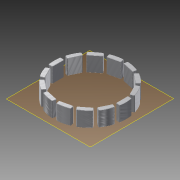
# Autodesk Inventor part: Magnets
Saved by Autodesk Inventor 2013 (Build 170138000, 138)
## iProperties
Created: 2013-09-29
Part Number: Magnets
Material: Generic
Document SubType Name: Modeling
Designer: Hunter
Density: 1 g/cm^3
Author: Hunter
Autodesk Inventor part; units mm, degrees
ref_plane "YZ Plane" through (0, 0, 0) normal (1, 0, 0) x (0, 1, 0)
ref_plane "XZ Plane" through (0, 0, 0) normal (0, 1, 0) x (-1, 0, 0)
ref_plane "XY Plane" through (0, 0, 0) normal (0, 0, 1) x (1, 0, 0)
ref_plane "Work Plane1" through (-207.9007, 98.1912, 0) normal (0, 0, 1) x (1, 0.0042, 0)
sketch "Sketch1" plane through (-207.9007, 98.1912, 0) normal (0, 0, 1) x (1, 0.0042, 0)
  circle A0 centre (0, 0) radius 20 construction
  line L0 (20.8053, 3.5) -> (20.8053, -3.5)
  line L1 (0, 0) -> (38.802, 0)
  line L2 (21.3053, 4) -> (22.9345, 4)
  line L3 (21.3053, -4) -> (22.9345, -4)
  arc A1 (23.4287, -3.5754) -> (23.4287, 3.5754) centre (0, 0) ccw
  arc A2 (21.3053, 4) -> (20.8053, 3.5) centre (21.3053, 3.5) ccw
  arc A3 (23.4287, 3.5754) -> (22.9345, 4) centre (22.9345, 3.5) ccw
  arc A4 (22.9345, -4) -> (23.4287, -3.5754) centre (22.9345, -3.5) ccw
  arc A5 (20.8053, -3.5) -> (21.3053, -4) centre (21.3053, -3.5) ccw
  line L4 (17.2263, 12.1805) -> (20.2635, 5.8737)
  line L5 (17.4599, 12.8479) -> (18.9277, 13.5548)
  line L6 (20.9309, 5.6401) -> (22.3988, 6.347)
  arc A6 (22.6599, 6.944) -> (19.5573, 13.3867) centre (0, 0) ccw
  arc A7 (17.4599, 12.8479) -> (17.2263, 12.1805) centre (17.6768, 12.3974) ccw
  arc A8 (19.5573, 13.3867) -> (18.9277, 13.5548) centre (19.1447, 13.1043) ccw
  arc A9 (22.3988, 6.347) -> (22.6599, 6.944) centre (22.1818, 6.7975) ccw
  arc A10 (20.2635, 5.8737) -> (20.9309, 5.6401) centre (20.714, 6.0906) ccw
  line L7 (10.2355, 18.4484) -> (15.7083, 14.084)
  line L8 (10.1563, 19.1511) -> (11.1721, 20.4249)
  line L9 (16.4109, 14.1632) -> (17.4267, 15.4369)
  arc A11 (17.403, 16.0881) -> (11.8122, 20.5466) centre (0, 0) ccw
  arc A12 (10.1563, 19.1511) -> (10.2355, 18.4484) centre (10.5472, 18.8393) ccw
  arc A13 (11.8122, 20.5466) -> (11.1721, 20.4249) centre (11.563, 20.1131) ccw
  arc A14 (17.4267, 15.4369) -> (17.403, 16.0881) centre (17.0358, 15.7487) ccw
  arc A15 (15.7083, 14.084) -> (16.4109, 14.1632) centre (16.02, 14.4749) ccw
  line L10 (1.2174, 21.0625) -> (8.0419, 19.5048)
  line L11 (0.8412, 21.6612) -> (1.2037, 23.2495)
  line L12 (8.6406, 19.881) -> (9.0031, 21.4694)
  arc A16 (8.6992, 22.0457) -> (1.7276, 23.6369) centre (0, 0) ccw
  arc A17 (0.8412, 21.6612) -> (1.2174, 21.0625) centre (1.3286, 21.5499) ccw
  arc A18 (1.7276, 23.6369) -> (1.2037, 23.2495) centre (1.6912, 23.1383) ccw
  arc A19 (9.0031, 21.4694) -> (8.6992, 22.0457) centre (8.5156, 21.5806) ccw
  arc A20 (8.0419, 19.5048) -> (8.6406, 19.881) centre (8.1531, 19.9923) ccw
  line L13 (-8.0419, 19.5048) -> (-1.2174, 21.0625)
  line L14 (-8.6406, 19.881) -> (-9.0031, 21.4694)
  line L15 (-0.8412, 21.6612) -> (-1.2037, 23.2495)
  arc A21 (-1.7276, 23.6369) -> (-8.6992, 22.0457) centre (0, 0) ccw
  arc A22 (-8.6406, 19.881) -> (-8.0419, 19.5048) centre (-8.1531, 19.9923) ccw
  arc A23 (-8.6992, 22.0457) -> (-9.0031, 21.4694) centre (-8.5156, 21.5806) ccw
  arc A24 (-1.2037, 23.2495) -> (-1.7276, 23.6369) centre (-1.6912, 23.1383) ccw
  arc A25 (-1.2174, 21.0625) -> (-0.8412, 21.6612) centre (-1.3286, 21.5499) ccw
  line L16 (-15.7083, 14.084) -> (-10.2355, 18.4484)
  line L17 (-16.4109, 14.1632) -> (-17.4267, 15.4369)
  line L18 (-10.1563, 19.1511) -> (-11.1721, 20.4249)
  arc A26 (-11.8122, 20.5466) -> (-17.403, 16.0881) centre (0, 0) ccw
  arc A27 (-16.4109, 14.1632) -> (-15.7083, 14.084) centre (-16.02, 14.4749) ccw
  arc A28 (-17.403, 16.0881) -> (-17.4267, 15.4369) centre (-17.0358, 15.7487) ccw
  arc A29 (-11.1721, 20.4249) -> (-11.8122, 20.5466) centre (-11.563, 20.1131) ccw
  arc A30 (-10.2355, 18.4484) -> (-10.1563, 19.1511) centre (-10.5472, 18.8393) ccw
  line L19 (-20.2635, 5.8737) -> (-17.2263, 12.1805)
  line L20 (-20.9309, 5.6401) -> (-22.3988, 6.347)
  line L21 (-17.4599, 12.8479) -> (-18.9277, 13.5548)
  arc A31 (-19.5573, 13.3867) -> (-22.6599, 6.944) centre (0, 0) ccw
  arc A32 (-20.9309, 5.6401) -> (-20.2635, 5.8737) centre (-20.714, 6.0906) ccw
  arc A33 (-22.6599, 6.944) -> (-22.3988, 6.347) centre (-22.1818, 6.7975) ccw
  arc A34 (-18.9277, 13.5548) -> (-19.5573, 13.3867) centre (-19.1447, 13.1043) ccw
  arc A35 (-17.2263, 12.1805) -> (-17.4599, 12.8479) centre (-17.6768, 12.3974) ccw
  line L22 (-20.8053, -3.5) -> (-20.8053, 3.5)
  line L23 (-21.3053, -4) -> (-22.9345, -4)
  line L24 (-21.3053, 4) -> (-22.9345, 4)
  arc A36 (-23.4287, 3.5754) -> (-23.4287, -3.5754) centre (0, 0) ccw
  arc A37 (-21.3053, -4) -> (-20.8053, -3.5) centre (-21.3053, -3.5) ccw
  arc A38 (-23.4287, -3.5754) -> (-22.9345, -4) centre (-22.9345, -3.5) ccw
  arc A39 (-22.9345, 4) -> (-23.4287, 3.5754) centre (-22.9345, 3.5) ccw
  arc A40 (-20.8053, 3.5) -> (-21.3053, 4) centre (-21.3053, 3.5) ccw
  line L25 (-17.2263, -12.1805) -> (-20.2635, -5.8737)
  line L26 (-17.4599, -12.8479) -> (-18.9277, -13.5548)
  line L27 (-20.9309, -5.6401) -> (-22.3988, -6.347)
  arc A41 (-22.6599, -6.944) -> (-19.5573, -13.3867) centre (0, 0) ccw
  arc A42 (-17.4599, -12.8479) -> (-17.2263, -12.1805) centre (-17.6768, -12.3974) ccw
  arc A43 (-19.5573, -13.3867) -> (-18.9277, -13.5548) centre (-19.1447, -13.1043) ccw
  arc A44 (-22.3988, -6.347) -> (-22.6599, -6.944) centre (-22.1818, -6.7975) ccw
  arc A45 (-20.2635, -5.8737) -> (-20.9309, -5.6401) centre (-20.714, -6.0906) ccw
  line L28 (-10.2355, -18.4484) -> (-15.7083, -14.084)
  line L29 (-10.1563, -19.1511) -> (-11.1721, -20.4249)
  line L30 (-16.4109, -14.1632) -> (-17.4267, -15.4369)
  arc A46 (-17.403, -16.0881) -> (-11.8122, -20.5466) centre (0, 0) ccw
  arc A47 (-10.1563, -19.1511) -> (-10.2355, -18.4484) centre (-10.5472, -18.8393) ccw
  arc A48 (-11.8122, -20.5466) -> (-11.1721, -20.4249) centre (-11.563, -20.1131) ccw
  arc A49 (-17.4267, -15.4369) -> (-17.403, -16.0881) centre (-17.0358, -15.7487) ccw
  arc A50 (-15.7083, -14.084) -> (-16.4109, -14.1632) centre (-16.02, -14.4749) ccw
  line L31 (-1.2174, -21.0625) -> (-8.0419, -19.5048)
  line L32 (-0.8412, -21.6612) -> (-1.2037, -23.2495)
  line L33 (-8.6406, -19.881) -> (-9.0031, -21.4694)
  arc A51 (-8.6992, -22.0457) -> (-1.7276, -23.6369) centre (0, 0) ccw
  arc A52 (-0.8412, -21.6612) -> (-1.2174, -21.0625) centre (-1.3286, -21.5499) ccw
  arc A53 (-1.7276, -23.6369) -> (-1.2037, -23.2495) centre (-1.6912, -23.1383) ccw
  arc A54 (-9.0031, -21.4694) -> (-8.6992, -22.0457) centre (-8.5156, -21.5806) ccw
  arc A55 (-8.0419, -19.5048) -> (-8.6406, -19.881) centre (-8.1531, -19.9923) ccw
  line L34 (8.0419, -19.5048) -> (1.2174, -21.0625)
  line L35 (8.6406, -19.881) -> (9.0031, -21.4694)
  line L36 (0.8412, -21.6612) -> (1.2037, -23.2495)
  arc A56 (1.7276, -23.6369) -> (8.6992, -22.0457) centre (0, 0) ccw
  arc A57 (8.6406, -19.881) -> (8.0419, -19.5048) centre (8.1531, -19.9923) ccw
  arc A58 (8.6992, -22.0457) -> (9.0031, -21.4694) centre (8.5156, -21.5806) ccw
  arc A59 (1.2037, -23.2495) -> (1.7276, -23.6369) centre (1.6912, -23.1383) ccw
  arc A60 (1.2174, -21.0625) -> (0.8412, -21.6612) centre (1.3286, -21.5499) ccw
  line L37 (15.7083, -14.084) -> (10.2355, -18.4484)
  line L38 (16.4109, -14.1632) -> (17.4267, -15.4369)
  line L39 (10.1563, -19.1511) -> (11.1721, -20.4249)
  arc A61 (11.8122, -20.5466) -> (17.403, -16.0881) centre (0, 0) ccw
  arc A62 (16.4109, -14.1632) -> (15.7083, -14.084) centre (16.02, -14.4749) ccw
  arc A63 (17.403, -16.0881) -> (17.4267, -15.4369) centre (17.0358, -15.7487) ccw
  arc A64 (11.1721, -20.4249) -> (11.8122, -20.5466) centre (11.563, -20.1131) ccw
  arc A65 (10.2355, -18.4484) -> (10.1563, -19.1511) centre (10.5472, -18.8393) ccw
  line L40 (20.2635, -5.8737) -> (17.2263, -12.1805)
  line L41 (20.9309, -5.6401) -> (22.3988, -6.347)
  line L42 (17.4599, -12.8479) -> (18.9277, -13.5548)
  arc A66 (19.5573, -13.3867) -> (22.6599, -6.944) centre (0, 0) ccw
  arc A67 (20.9309, -5.6401) -> (20.2635, -5.8737) centre (20.714, -6.0906) ccw
  arc A68 (22.6599, -6.944) -> (22.3988, -6.347) centre (22.1818, -6.7975) ccw
  arc A69 (18.9277, -13.5548) -> (19.5573, -13.3867) centre (19.1447, -13.1043) ccw
  arc A70 (17.2263, -12.1805) -> (17.4599, -12.8479) centre (17.6768, -12.3974) ccw
  point P0 (207.4817, -99.0734)
  point P1 (20.8053, 0)
  point P2 (23.36, 4)
  point P3 (23.36, -4)
  point P4 (18.7449, 9.0271)
  point P5 (19.3111, 13.7394)
  point P6 (22.7822, 6.5317)
  point P7 (12.9719, 16.2662)
  point P8 (11.4374, 20.7575)
  point P9 (17.6921, 15.7696)
  point P10 (4.6296, 20.2836)
  point P11 (1.2984, 23.6644)
  point P12 (9.0978, 21.8842)
  point P13 (-4.6296, 20.2836)
  point P14 (-9.0978, 21.8842)
  point P15 (-1.2984, 23.6644)
  point P16 (-12.9719, 16.2662)
  point P17 (-17.6921, 15.7696)
  point P18 (-11.4374, 20.7575)
  point P19 (-18.7449, 9.0271)
  point P20 (-22.7822, 6.5317)
  point P21 (-19.3111, 13.7394)
  point P22 (-20.8053, 0)
  point P23 (-23.36, -4)
  point P24 (-23.36, 4)
  point P25 (-18.7449, -9.0271)
  point P26 (-19.3111, -13.7394)
  point P27 (-22.7822, -6.5317)
  point P28 (-12.9719, -16.2662)
  point P29 (-11.4374, -20.7575)
  point P30 (-17.6921, -15.7696)
  point P31 (-4.6296, -20.2836)
  point P32 (-1.2984, -23.6644)
  point P33 (-9.0978, -21.8842)
  point P34 (4.6296, -20.2836)
  point P35 (9.0978, -21.8842)
  point P36 (1.2984, -23.6644)
  point P37 (12.9719, -16.2662)
  point P38 (17.6921, -15.7696)
  point P39 (11.4374, -20.7575)
  point P40 (18.7449, -9.0271)
  point P41 (22.7822, -6.5317)
  point P42 (19.3111, -13.7394)
  dimension "d0" = 40
  dimension "d7" = 8
  dimension "d8" = 0.5
  dimension "d11" = 360
  constraints: 168 point on circle, 86 end point, 71 centre point, 30 point on line, 8 tangent, 3 equal radius, 2 parallel, 1 horizontal, 1 midpoint, 1 perpendicular, 338 other
  measures "d0" diameter of A0
  measures "d7" distance between parallel lines of L3 L2
  measures "d8" radius of A2
extrude "Extrusion1" add sketch "Sketch1" along normal blind 10
chamfer "Chamfer1" distance 0.2 angle 45 224 edges at (-203.3573, 118.4943, 10) (-199.5647, 117.7957, 10) (-199.1667, 118.9036, 10) (-199.0355, 120.0429, 10) (-202.7251, 121.3191, 10) (-206.6068, 121.7372, 10) (-206.9737, 120.6507, 10) (-207.0858, 119.4787, 10) (-194.998, 114.5123, 10) (-191.8842, 112.2374, 10) (-191.0449, 113.0629, 10) (-190.4323, 114.0324, 10) (-193.2028, 116.7832, 10) (-196.5187, 118.844, 10) (-197.3206, 118.0242, 10) (-197.9302, 117.017, 10) (-212.6164, 118.455, 10) (-208.8963, 119.471, 10) (-209.0185, 120.642, 10) (-209.3945, 121.7253, 10) (-213.2725, 121.2743, 10) (-216.9512, 119.9668, 10) (-216.8103, 118.8287, 10) (-216.4029, 117.7241, 10) (-220.9415, 114.4021, 10) (-218.0307, 116.9317, 10) (-218.6488, 117.9337, 10) (-219.4577, 118.7466, 10) (-222.756, 116.6576, 10) (-225.503, 113.8834, 10) (-224.8822, 112.9192, 10) (-224.0359, 112.1008, 10) (-226.6838, 107.1385, 10) (-225.1587, 110.6805, 10) (-226.1504, 111.3151, 10) (-227.2318, 111.6965, 10) (-229.2971, 108.3834, 10) (-230.5684, 104.6921, 10) (-229.5908, 104.0927, 10) (-228.4732, 103.7225, 10) (-228.7058, 98.1028, 10) (-228.8686, 101.9557, 10) (-230.0373, 102.0972, 10) (-231.1772, 101.9716, 10) (-231.6005, 98.0905, 10) (-231.1443, 94.2131, 10) (-230.0034, 94.0972, 10) (-228.8358, 94.2486, 10) (-226.6071, 89.0845, 10) (-228.4255, 92.4852, 10) (-229.5399, 92.1056, 10) (-230.5124, 91.4979, 10) (-229.2098, 87.8175, 10) (-227.1164, 84.522, 10) (-226.0382, 84.9127, 10) (-225.052, 85.5556, 10) (-220.8033, 81.87, 10) (-223.9172, 84.1449, 10) (-224.7565, 83.3194, 10) (-225.369, 82.3499, 10) (-222.5985, 79.5992, 10) (-219.2826, 77.5383, 10) (-218.4807, 78.3581, 10) (-217.8712, 79.3653, 10) (-212.4441, 77.888, 10) (-216.2366, 78.5867, 10) (-216.6346, 77.4787, 10) (-216.7659, 76.3394, 10) (-213.0762, 75.0632, 10) (-209.1945, 74.6451, 10) (-208.8277, 75.7317, 10) (-208.7155, 76.9036, 10) (-203.185, 77.9274, 10) (-206.905, 76.9113, 10) (-206.7829, 75.7403, 10) (-206.4068, 74.657, 10) (-202.5288, 75.108, 10) (-198.8502, 76.4155, 10) (-198.9911, 77.5536, 10) (-199.3985, 78.6582, 10) (-194.8598, 81.9802, 10) (-197.7706, 79.4507, 10) (-197.1525, 78.4487, 10) (-196.3437, 77.6358, 10) (-193.0454, 79.7247, 10) (-190.2984, 82.4989, 10) (-190.9191, 83.4631, 10) (-191.7654, 84.2815, 10) (-189.1176, 89.2438, 10) (-190.6426, 85.7018, 10) (-189.651, 85.0672, 10) (-188.5695, 84.6858, 10) (-186.5042, 87.9989, 10) (-185.2329, 91.6902, 10) (-186.2106, 92.2897, 10) (-187.3282, 92.6598, 10) (-185.764, 94.2852, 10) (-184.6241, 94.4107, 10) (-184.2009, 98.2918, 10) (-184.6571, 102.1692, 10) (-185.798, 102.2851, 10) (-186.9655, 102.1337, 10) (-187.0956, 98.2795, 10) (-186.9328, 94.4266, 10) (-187.3759, 103.8971, 10) (-186.2615, 104.2767, 10) (-185.289, 104.8844, 10) (-186.5916, 108.5648, 10) (-188.685, 111.8603, 10) (-189.7631, 111.4696, 10) (-190.7493, 110.8267, 10) (-189.1943, 107.2978, 10) (-194.998, 114.5123, 0) (-191.8842, 112.2374, 0) (-191.0449, 113.0629, 0) (-190.4323, 114.0324, 0) (-193.2028, 116.7832, 0) (-196.5187, 118.844, 0) (-197.3206, 118.0242, 0) (-197.9302, 117.017, 0) (-199.5647, 117.7957, 0) (-199.1667, 118.9036, 0) (-199.0355, 120.0429, 0) (-202.7251, 121.3191, 0) (-206.6068, 121.7372, 0) (-206.9737, 120.6507, 0) (-207.0858, 119.4787, 0) (-203.3573, 118.4943, 0) (-212.6164, 118.455, 0) (-208.8963, 119.471, 0) (-209.0185, 120.642, 0) (-209.3945, 121.7253, 0) (-213.2725, 121.2743, 0) (-216.9512, 119.9668, 0) (-216.8103, 118.8287, 0) (-216.4029, 117.7241, 0) (-220.9415, 114.4021, 0) (-218.0307, 116.9317, 0) (-218.6488, 117.9337, 0) (-219.4577, 118.7466, 0) (-222.756, 116.6576, 0) (-225.503, 113.8834, 0) (-224.8822, 112.9192, 0) (-224.0359, 112.1008, 0) (-226.6838, 107.1385, 0) (-225.1587, 110.6805, 0) (-226.1504, 111.3151, 0) (-227.2318, 111.6965, 0) (-229.2971, 108.3834, 0) (-230.5684, 104.6921, 0) (-229.5908, 104.0927, 0) (-228.4732, 103.7225, 0) (-228.7058, 98.1028, 0) (-228.8686, 101.9557, 0) (-230.0373, 102.0972, 0) (-231.1772, 101.9716, 0) (-231.6005, 98.0905, 0) (-231.1443, 94.2131, 0) (-230.0034, 94.0972, 0) (-228.8358, 94.2486, 0) (-226.0382, 84.9127, 0) (-225.052, 85.5556, 0) (-226.6071, 89.0845, 0) (-228.4255, 92.4852, 0) (-229.5399, 92.1056, 0) (-230.5124, 91.4979, 0) (-229.2098, 87.8175, 0) (-227.1164, 84.522, 0) (-222.5985, 79.5992, 0) (-219.2826, 77.5383, 0) (-218.4807, 78.3581, 0) (-217.8712, 79.3653, 0) (-220.8033, 81.87, 0) (-223.9172, 84.1449, 0) (-224.7565, 83.3194, 0) (-225.369, 82.3499, 0) (-213.0762, 75.0632, 0) (-209.1945, 74.6451, 0) (-208.8277, 75.7317, 0) (-208.7155, 76.9036, 0) (-212.4441, 77.888, 0) (-216.2366, 78.5867, 0) (-216.6346, 77.4787, 0) (-216.7659, 76.3394, 0) (-202.5288, 75.108, 0) (-198.8502, 76.4155, 0) (-198.9911, 77.5536, 0) (-199.3985, 78.6582, 0) (-203.185, 77.9274, 0) (-206.905, 76.9113, 0) (-206.7829, 75.7403, 0) (-206.4068, 74.657, 0) (-193.0454, 79.7247, 0) (-190.2984, 82.4989, 0) (-190.9191, 83.4631, 0) (-191.7654, 84.2815, 0) (-194.8598, 81.9802, 0) (-197.7706, 79.4507, 0) (-197.1525, 78.4487, 0) (-196.3437, 77.6358, 0) (-186.5042, 87.9989, 0) (-185.2329, 91.6902, 0) (-186.2106, 92.2897, 0) (-187.3282, 92.6598, 0) (-189.1176, 89.2438, 0) (-190.6426, 85.7018, 0) (-189.651, 85.0672, 0) (-188.5695, 84.6858, 0) (-185.764, 94.2852, 0) (-184.6241, 94.4107, 0) (-184.2009, 98.2918, 0) (-184.6571, 102.1692, 0) (-185.798, 102.2851, 0) (-186.9655, 102.1337, 0) (-187.0956, 98.2795, 0) (-186.9328, 94.4266, 0) (-189.1943, 107.2978, 0) (-187.3759, 103.8971, 0) (-186.2615, 104.2767, 0) (-185.289, 104.8844, 0) (-186.5916, 108.5648, 0) (-188.685, 111.8603, 0) (-189.7631, 111.4696, 0) (-190.7493, 110.8267, 0)
body "Solid1"
